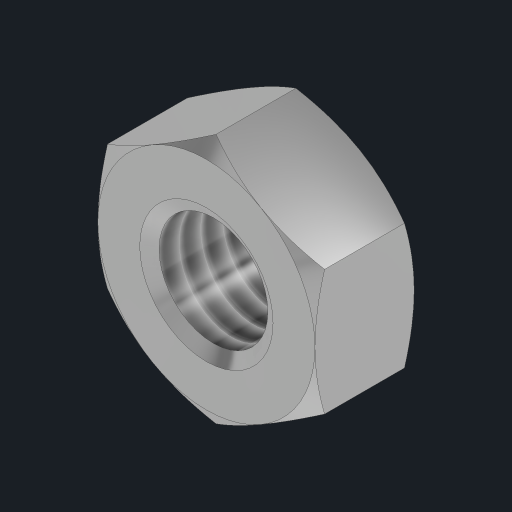
# Autodesk Inventor part: Porca Sextavada DIN 934 - M4 - 8
Saved by Autodesk Inventor 2024.3 (Build 283343000, 343)
## iProperties
Created: 2025-07-13
Part Number: Porca Sextavada DIN 934 - M4 - 8
Material: Aço inoxidável
Document SubType Name: Modeling
Designer: Cliente
Mass: 0.824132 g
Surface Area: 1.70892 cm^2
Volume: 0.103016 cm^3
Density: 8 g/cm^3
Appearance: Aço inoxidável - Brilhoso
Author: Cliente
Autodesk Inventor part; units mm, degrees
ref_plane "YZ Plane" through (0, 0, 0) normal (1, 0, 0) x (0, 1, 0)
ref_plane "XZ Plane" through (0, 0, 0) normal (0, 1, 0) x (-1, 0, 0)
ref_plane "XY Plane" through (0, 0, 0) normal (0, 0, 1) x (1, 0, 0)
sketch "Esboço1" plane through (0, 0, 0) normal (0, 0, 1) x (1, 0, 0)
  line L0 (0, 4.0415) -> (3.5, 2.0207)
  line L1 (3.5, 2.0207) -> (3.5, -2.0207)
  line L2 (3.5, -2.0207) -> (0, -4.0415)
  line L3 (0, -4.0415) -> (-3.5, -2.0207)
  line L4 (-3.5, -2.0207) -> (-3.5, 2.0207)
  line L5 (-3.5, 2.0207) -> (0, 4.0415)
  circle A0 centre (0, 0) radius 1.755
  dimension "d0" = 7
  dimension "d1" = 3.51
  constraints: 12 end point, 2 coincident, 1 centre point, 1 vertical alignment, 13 other
  measures "d0" distance between parallel lines of L1 L4
  measures "d1" diameter of A0
extrude "Extrusão1" add sketch "Esboço1" along normal blind 3.2
sketch "Esboço2" plane through (0, 0, 0) normal (1, 0, 0) x (0, 1, 0)
  line L0 (4.0415, 0) -> (2.0207, 0) projected
  line L1 (2.0207, 0) -> (2.0207, 3.2) projected
  line L2 (4.0415, 3.2) -> (2.0207, 3.2) projected
  line L3 (4.0415, 0) -> (4.0415, 3.2) projected
  line L4 (1.755, 3.2) -> (1.755, 0) projected
  line L5 (0, 0) -> (2.15, 0)
  line L6 (2.15, 0) -> (1.755, 0.2281)
  line L7 (0, 0) -> (3.5, 0)
  line L8 (3.5, 0) -> (4.0415, 0.3126)
  line L9 (3.5, 0) -> (4.1252, 0) construction
  line L10 (0, -0.48) -> (0, 2.88) projected
  line L11 (0, 1.6) -> (1.755, 1.6)
  line L12 (0, 3.2) -> (2.15, 3.2)
  line L13 (2.15, 3.2) -> (1.755, 2.9719)
  line L14 (3.5, 3.2) -> (4.0415, 2.8874)
  point P0 (2.0207, 0.0746)
  point P1 (3.5, 3.2)
  point P2 (1.755, 0)
  dimension "d4" = 2.15
  dimension "d5" = 30
  dimension "d6" = 3.5
  dimension "d7" = 30
  constraints: 18 end point, 5 point on line, 5 symmetric about line, 2 horizontal, 1 equal length, 1 midpoint
  measures "d4" distance of L5.start L5.end
  measures "d5" angle of L6 L5
  measures "d6" distance of L5.start L7.end
  measures "d7" angle of L9 L8
revolve "Revolução1" cut sketch "Esboço2" angle 360 about axis through (0, 0, -10) along (0, 0, 1) contours L0 L8 L3 | L0 L1 L6 | L14 L2 L3 | L5 L4 L6 L1 | L13 L4 L12 L1 | L1 L2 L13
thread "Rosca1" size "M4x0.7" class "6H" standard "ANSI Metric M Profile" full length
